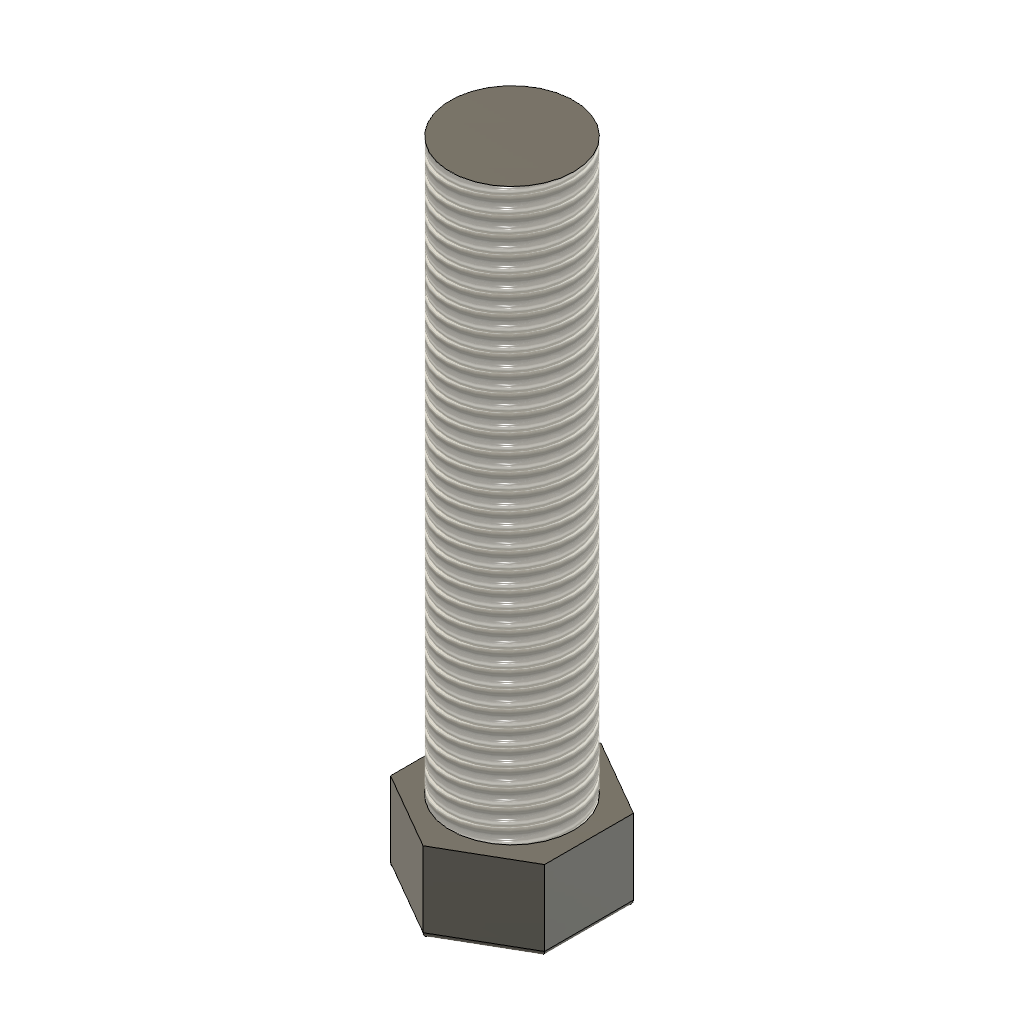
tornillo_contrapeso (Autodesk Fusion 360 design; units mm, degrees)
Autodesk Fusion 360 part; units mm, degrees
sketch "Boceto1" plane through (0, 0, 0) normal (0, 1, 0) x (1, 0, 0)
  circle A0 centre (0, 0) radius 7.8 construction
  line L0 (0, 7.8) -> (-6.755, 3.9)
  line L1 (-6.755, 3.9) -> (-6.755, -3.9)
  line L2 (-6.755, -3.9) -> (0, -7.8)
  line L3 (0, -7.8) -> (6.755, -3.9)
  line L4 (6.755, -3.9) -> (6.755, 3.9)
  line L5 (6.755, 3.9) -> (0, 7.8)
  dimension "d1" = 15.6
  constraint coincident A0.centre origin
  constraint coincident A0 L0.start
  measures "d1" diameter of A0
extrude "Extruir1" add sketch "Boceto1" along normal blind 7.1
sketch "Boceto2" plane through (0, 7.1, 0) normal (0, 1, 0) x (-1, 0, 0)
  line L0 (-6.755, -3.9) -> (0, -7.8)
  line L1 (0, -7.8) -> (6.755, -3.9)
  line L2 (6.755, -3.9) -> (6.755, 3.9)
  line L3 (6.755, 3.9) -> (0, 7.8)
  line L4 (0, 7.8) -> (-6.755, 3.9)
  line L5 (-6.755, 3.9) -> (-6.755, -3.9)
  circle A0 centre (0, 0) radius 5.5
  dimension "d4" = 11
  constraint coincident A0.centre origin
  measures "d4" diameter of A0
extrude "Extruir2" add sketch "Boceto2" along normal blind 50 contours A0
thread "Rosca1" "ISO Metric profile 11.0 M11x1.5 M11x1.5 6g" major diameter 10.85 minor diameter 9.1409 pitch 1.5 angle 60 resizes the face on face at (-5.4727, 23.7667, -0.5476)
fillet "Empalme1" radius 0.5 6 edges at (-3.3775, 0, -5.85) (3.3775, 0, -5.85) (6.755, 0, 0) (3.3775, 0, 5.85) (-3.3775, 0, 5.85) (-6.755, 0, 0)
